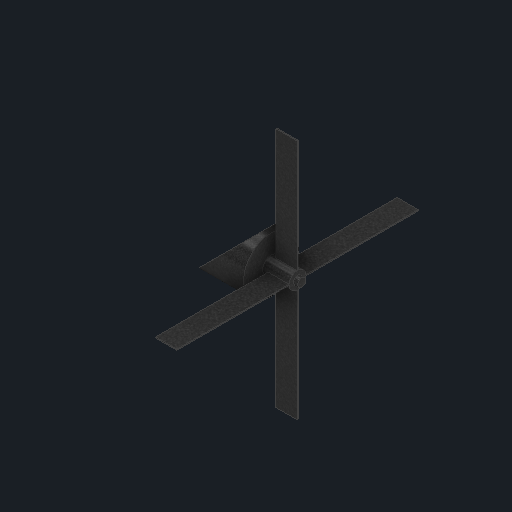
# Autodesk Inventor part: c8n_secondary_spider
Saved by Autodesk Inventor 2027.1 (Build 311270010, 270A)
## iProperties
Created: 2026-11-04
Part Number: c8n_secondary_spider
Material: Generic
Description: 4-vane spider + secondary holder
Document SubType Name: Modeling
Designer: Claude (from photos)
Density: 1 g/cm^3
Appearance: Black Cast
Author: alexg
Autodesk Inventor part; units mm, degrees
ref_plane "Work Plane1" through (812, 0, 0) normal (1, 0, 0) x (0, 1, 0)
sketch "Secondary holder sketch" plane through (812, 0, 0) normal (1, 0, 0) x (0, 1, 0)
  circle A0 centre (0, 0) radius 26
  constraints: 1 centre point
extrude "Secondary holder" add sketch "Secondary holder sketch" along normal blind 70
sketch "45 deg face sketch" plane through (0, 0, 0) normal (0, 0, 1) x (1, 0, 0)
  line L0 (762, -40) -> (810.4853, -40)
  line L1 (810.4853, -40) -> (890.4853, 40)
  line L2 (890.4853, 40) -> (762, 40)
  line L3 (762, 40) -> (762, -40)
  constraints: 8 end point
extrude "45 deg face" cut sketch "45 deg face sketch" along normal mid plane 80
ref_plane "Work Plane2" through (882, 0, 0) normal (1, 0, 0) x (0, 1, 0)
sketch "Spider hub sketch" plane through (882, 0, 0) normal (1, 0, 0) x (0, 1, 0)
  circle A0 centre (0, 0) radius 8
  constraints: 1 centre point
extrude "Spider hub" add sketch "Spider hub sketch" along normal blind 25
ref_plane "Work Plane3" through (907, 0, 0) normal (1, 0, 0) x (0, 1, 0)
sketch "Centre bolt sketch" plane through (907, 0, 0) normal (1, 0, 0) x (0, 1, 0)
  circle A0 centre (0, 0) radius 4
  constraints: 1 centre point
extrude "Centre bolt" add sketch "Centre bolt sketch" along normal blind 4
ref_plane "Work Plane4" through (887, 0, 0) normal (1, 0, 0) x (0, 1, 0)
sketch "Spider vanes x4 sketch" plane through (887, 0, 0) normal (1, 0, 0) x (0, 1, 0)
  line L0 (7, -0.5) -> (113.95, -0.5)
  line L1 (113.95, -0.5) -> (113.95, 0.5)
  line L2 (113.95, 0.5) -> (7, 0.5)
  line L3 (7, 0.5) -> (7, -0.5)
  line L4 (-113.95, -0.5) -> (-7, -0.5)
  line L5 (-7, -0.5) -> (-7, 0.5)
  line L6 (-7, 0.5) -> (-113.95, 0.5)
  line L7 (-113.95, 0.5) -> (-113.95, -0.5)
  line L8 (-0.5, 7) -> (0.5, 7)
  line L9 (0.5, 7) -> (0.5, 113.95)
  line L10 (0.5, 113.95) -> (-0.5, 113.95)
  line L11 (-0.5, 113.95) -> (-0.5, 7)
  line L12 (-0.5, -113.95) -> (0.5, -113.95)
  line L13 (0.5, -113.95) -> (0.5, -7)
  line L14 (0.5, -7) -> (-0.5, -7)
  line L15 (-0.5, -7) -> (-0.5, -113.95)
  constraints: 32 end point, 8 parallel, 4 horizontal, 4 perpendicular
extrude "Spider vanes x4" add sketch "Spider vanes x4 sketch" along normal blind 20
body "Solid1"
